Autodesk Fusion 360 part; units mm, degrees
(part 20 of 28)
  line L3105 (96.8519, 73.2833) -> (96.6596, 73.2451)
  line L3106 (96.6596, 73.2451) -> (96.4636, 73.2451)
  line L3107 (96.4636, 73.2451) -> (96.2713, 73.2833)
  line L3108 (96.2713, 73.2833) -> (96.0902, 73.3584)
  line L3109 (96.0902, 73.3584) -> (95.9272, 73.4673)
  line L3110 (95.9272, 73.4673) -> (95.7886, 73.6059)
  line L3111 (95.7886, 73.6059) -> (95.6797, 73.7689)
  line L3112 (95.6797, 73.7689) -> (95.6047, 73.95)
  line L3113 (95.6047, 73.95) -> (95.5664, 74.1423)
  line L3114 (95.5664, 74.1423) -> (95.5616, 74.2403)
  line L3115 (95.5616, 74.2403) -> (95.5616, 75.4403)
  line L3116 (95.5616, 75.4403) -> (95.5664, 75.5383)
  line L3117 (95.5664, 75.5383) -> (95.6047, 75.7306)
  line L3118 (95.6047, 75.7306) -> (95.6797, 75.9117)
  line L3119 (95.6797, 75.9117) -> (95.7886, 76.0747)
  line L3120 (95.7886, 76.0747) -> (95.9272, 76.2133)
  line L3121 (95.9272, 76.2133) -> (96.0902, 76.3222)
  line L3122 (96.0902, 76.3222) -> (96.2713, 76.3972)
  line L3123 (96.2713, 76.3972) -> (96.4636, 76.4355)
  line L3124 (96.4636, 76.4355) -> (96.6596, 76.4355)
  line L3125 (96.6596, 76.4355) -> (96.8519, 76.3972)
  line L3126 (99.5819, 76.3972) -> (99.763, 76.3222)
  line L3127 (99.763, 76.3222) -> (99.926, 76.2133)
  line L3128 (99.926, 76.2133) -> (100.0646, 76.0747)
  line L3129 (100.0646, 76.0747) -> (100.1735, 75.9117)
  line L3130 (100.1735, 75.9117) -> (100.2485, 75.7306)
  line L3131 (100.2485, 75.7306) -> (100.2868, 75.5383)
  line L3132 (100.2868, 75.5383) -> (100.2916, 75.4403)
  line L3133 (100.2916, 75.4403) -> (100.2916, 74.2403)
  line L3134 (100.2916, 74.2403) -> (100.2868, 74.1423)
  line L3135 (100.2868, 74.1423) -> (100.2485, 73.95)
  line L3136 (100.2485, 73.95) -> (100.1735, 73.7689)
  line L3137 (100.1735, 73.7689) -> (100.0646, 73.6059)
  line L3138 (100.0646, 73.6059) -> (99.926, 73.4673)
  line L3139 (99.926, 73.4673) -> (99.763, 73.3584)
  line L3140 (99.763, 73.3584) -> (99.5819, 73.2833)
  line L3141 (99.5819, 73.2833) -> (99.3896, 73.2451)
  line L3142 (99.3896, 73.2451) -> (99.1936, 73.2451)
  line L3143 (99.1936, 73.2451) -> (99.0013, 73.2833)
  line L3144 (99.0013, 73.2833) -> (98.8202, 73.3584)
  line L3145 (98.8202, 73.3584) -> (98.6572, 73.4673)
  line L3146 (98.6572, 73.4673) -> (98.5186, 73.6059)
  line L3147 (98.5186, 73.6059) -> (98.4097, 73.7689)
  line L3148 (98.4097, 73.7689) -> (98.3347, 73.95)
  line L3149 (98.3347, 73.95) -> (98.2964, 74.1423)
  line L3150 (98.2964, 74.1423) -> (98.2916, 74.2403)
  line L3151 (98.2916, 74.2403) -> (98.2916, 75.4403)
  line L3152 (98.2916, 75.4403) -> (98.2964, 75.5383)
  line L3153 (98.2964, 75.5383) -> (98.3347, 75.7306)
  line L3154 (98.3347, 75.7306) -> (98.4097, 75.9117)
  line L3155 (98.4097, 75.9117) -> (98.5186, 76.0747)
  line L3156 (98.5186, 76.0747) -> (98.6572, 76.2133)
  line L3157 (98.6572, 76.2133) -> (98.8202, 76.3222)
  line L3158 (98.8202, 76.3222) -> (99.0013, 76.3972)
  line L3159 (99.0013, 76.3972) -> (99.1936, 76.4355)
  line L3160 (99.1936, 76.4355) -> (99.3896, 76.4355)
  line L3161 (99.3896, 76.4355) -> (99.5819, 76.3972)
  line L3162 (131.7769, 76.3972) -> (131.958, 76.3222)
  line L3163 (131.958, 76.3222) -> (132.121, 76.2133)
  line L3164 (132.121, 76.2133) -> (132.2596, 76.0747)
  line L3165 (132.2596, 76.0747) -> (132.3685, 75.9117)
  line L3166 (132.3685, 75.9117) -> (132.4435, 75.7306)
  line L3167 (132.4435, 75.7306) -> (132.4818, 75.5383)
  line L3168 (132.4818, 75.5383) -> (132.4866, 75.4403)
  line L3169 (132.4866, 75.4403) -> (132.4866, 74.2403)
  line L3170 (132.4866, 74.2403) -> (132.4818, 74.1423)
  line L3171 (132.4818, 74.1423) -> (132.4435, 73.95)
  line L3172 (132.4435, 73.95) -> (132.3685, 73.7689)
  line L3173 (132.3685, 73.7689) -> (132.2596, 73.6059)
  line L3174 (132.2596, 73.6059) -> (132.121, 73.4673)
  line L3175 (132.121, 73.4673) -> (131.958, 73.3584)
  line L3176 (131.958, 73.3584) -> (131.7769, 73.2833)
  line L3177 (131.7769, 73.2833) -> (131.5846, 73.2451)
  line L3178 (131.5846, 73.2451) -> (131.3886, 73.2451)
  line L3179 (131.3886, 73.2451) -> (131.1963, 73.2833)
  line L3180 (131.1963, 73.2833) -> (131.0152, 73.3584)
  line L3181 (131.0152, 73.3584) -> (130.8522, 73.4673)
  line L3182 (130.8522, 73.4673) -> (130.7136, 73.6059)
  line L3183 (130.7136, 73.6059) -> (130.6047, 73.7689)
  line L3184 (130.6047, 73.7689) -> (130.5297, 73.95)
  line L3185 (130.5297, 73.95) -> (130.4914, 74.1423)
  line L3186 (130.4914, 74.1423) -> (130.4866, 74.2403)
  line L3187 (130.4866, 74.2403) -> (130.4866, 75.4403)
  line L3188 (130.4866, 75.4403) -> (130.4914, 75.5383)
  line L3189 (130.4914, 75.5383) -> (130.5297, 75.7306)
  line L3190 (130.5297, 75.7306) -> (130.6047, 75.9117)
  line L3191 (130.6047, 75.9117) -> (130.7136, 76.0747)
  line L3192 (130.7136, 76.0747) -> (130.8522, 76.2133)
  line L3193 (130.8522, 76.2133) -> (131.0152, 76.3222)
  line L3194 (131.0152, 76.3222) -> (131.1963, 76.3972)
  line L3195 (131.1963, 76.3972) -> (131.3886, 76.4355)
  line L3196 (131.3886, 76.4355) -> (131.5846, 76.4355)
  line L3197 (131.5846, 76.4355) -> (131.7769, 76.3972)
  line L3198 (134.5069, 76.3972) -> (134.688, 76.3222)
  line L3199 (134.688, 76.3222) -> (134.851, 76.2133)
  line L3200 (134.851, 76.2133) -> (134.9896, 76.0747)
  line L3201 (134.9896, 76.0747) -> (135.0985, 75.9117)
  line L3202 (135.0985, 75.9117) -> (135.1735, 75.7306)
  line L3203 (135.1735, 75.7306) -> (135.2118, 75.5383)
  line L3204 (135.2118, 75.5383) -> (135.2166, 75.4403)
  line L3205 (135.2166, 75.4403) -> (135.2166, 74.2403)
  line L3206 (135.2166, 74.2403) -> (135.2118, 74.1423)
  line L3207 (135.2118, 74.1423) -> (135.1735, 73.95)
  line L3208 (135.1735, 73.95) -> (135.0985, 73.7689)
  line L3209 (135.0985, 73.7689) -> (134.9896, 73.6059)
  line L3210 (134.9896, 73.6059) -> (134.851, 73.4673)
  line L3211 (134.851, 73.4673) -> (134.688, 73.3584)
  line L3212 (134.688, 73.3584) -> (134.5069, 73.2833)
  line L3213 (134.5069, 73.2833) -> (134.3146, 73.2451)
  line L3214 (134.3146, 73.2451) -> (134.1186, 73.2451)
  line L3215 (134.1186, 73.2451) -> (133.9263, 73.2833)
  line L3216 (133.9263, 73.2833) -> (133.7452, 73.3584)
  line L3217 (133.7452, 73.3584) -> (133.5822, 73.4673)
  line L3218 (133.5822, 73.4673) -> (133.4436, 73.6059)
  line L3219 (133.4436, 73.6059) -> (133.3347, 73.7689)
  line L3220 (133.3347, 73.7689) -> (133.2597, 73.95)
  line L3221 (133.2597, 73.95) -> (133.2214, 74.1423)
  line L3222 (133.2214, 74.1423) -> (133.2166, 74.2403)
  line L3223 (133.2166, 74.2403) -> (133.2166, 75.4403)
  line L3224 (133.2166, 75.4403) -> (133.2214, 75.5383)
  line L3225 (133.2214, 75.5383) -> (133.2597, 75.7306)
  line L3226 (133.2597, 75.7306) -> (133.3347, 75.9117)
  line L3227 (133.3347, 75.9117) -> (133.4436, 76.0747)
  line L3228 (133.4436, 76.0747) -> (133.5822, 76.2133)
  line L3229 (133.5822, 76.2133) -> (133.7452, 76.3222)
  line L3230 (133.7452, 76.3222) -> (133.9263, 76.3972)
  line L3231 (133.9263, 76.3972) -> (134.1186, 76.4355)
  line L3232 (134.1186, 76.4355) -> (134.3146, 76.4355)
  line L3233 (134.3146, 76.4355) -> (134.5069, 76.3972)
  line L3234 (14.4065, 73.2985) -> (12.4065, 73.2985)
  line L3235 (12.4065, 73.2985) -> (12.4065, 76.4985)
  line L3236 (12.4065, 76.4985) -> (14.4065, 76.4985)
  line L3237 (14.4065, 76.4985) -> (14.4065, 73.2985)
  line L3238 (49.3315, 73.2985) -> (47.3315, 73.2985)
  line L3239 (47.3315, 73.2985) -> (47.3315, 76.4985)
  line L3240 (47.3315, 76.4985) -> (49.3315, 76.4985)
  line L3241 (49.3315, 76.4985) -> (49.3315, 73.2985)
  line L3242 (84.2565, 73.2985) -> (82.2565, 73.2985)
  line L3243 (82.2565, 73.2985) -> (82.2565, 76.4985)
  line L3244 (82.2565, 76.4985) -> (84.2565, 76.4985)
  line L3245 (84.2565, 76.4985) -> (84.2565, 73.2985)
  line L3246 (119.1815, 73.2985) -> (117.1815, 73.2985)
  line L3247 (117.1815, 73.2985) -> (117.1815, 76.4985)
  line L3248 (117.1815, 76.4985) -> (119.1815, 76.4985)
  line L3249 (119.1815, 76.4985) -> (119.1815, 73.2985)
  line L3250 (16.4668, 76.4554) -> (16.6479, 76.3804)
  line L3251 (16.6479, 76.3804) -> (16.8109, 76.2715)
  line L3252 (16.8109, 76.2715) -> (16.9495, 76.1329)
  line L3253 (16.9495, 76.1329) -> (17.0584, 75.9699)
  line L3254 (17.0584, 75.9699) -> (17.1335, 75.7888)
  line L3255 (17.1335, 75.7888) -> (17.1717, 75.5965)
  line L3256 (17.1717, 75.5965) -> (17.1765, 75.4985)
  line L3257 (17.1765, 75.4985) -> (17.1765, 74.2985)
  line L3258 (17.1765, 74.2985) -> (17.1717, 74.2005)
  line L3259 (17.1717, 74.2005) -> (17.1335, 74.0082)
  line L3260 (17.1335, 74.0082) -> (17.0584, 73.8271)
  line L3261 (17.0584, 73.8271) -> (16.9495, 73.6641)
  line L3262 (16.9495, 73.6641) -> (16.8109, 73.5255)
  line L3263 (16.8109, 73.5255) -> (16.6479, 73.4166)
  line L3264 (16.6479, 73.4166) -> (16.4668, 73.3415)
  line L3265 (16.4668, 73.3415) -> (16.2745, 73.3033)
  line L3266 (16.2745, 73.3033) -> (16.0785, 73.3033)
  line L3267 (16.0785, 73.3033) -> (15.8862, 73.3415)
  line L3268 (15.8862, 73.3415) -> (15.7051, 73.4166)
  line L3269 (15.7051, 73.4166) -> (15.5421, 73.5255)
  line L3270 (15.5421, 73.5255) -> (15.4035, 73.6641)
  line L3271 (15.4035, 73.6641) -> (15.2946, 73.8271)
  line L3272 (15.2946, 73.8271) -> (15.2196, 74.0082)
  line L3273 (15.2196, 74.0082) -> (15.1813, 74.2005)
  line L3274 (15.1813, 74.2005) -> (15.1765, 74.2985)
  line L3275 (15.1765, 74.2985) -> (15.1765, 75.4985)
  line L3276 (15.1765, 75.4985) -> (15.1813, 75.5965)
  line L3277 (15.1813, 75.5965) -> (15.2196, 75.7888)
  line L3278 (15.2196, 75.7888) -> (15.2946, 75.9699)
  line L3279 (15.2946, 75.9699) -> (15.4035, 76.1329)
  line L3280 (15.4035, 76.1329) -> (15.5421, 76.2715)
  line L3281 (15.5421, 76.2715) -> (15.7051, 76.3804)
  line L3282 (15.7051, 76.3804) -> (15.8862, 76.4554)
  line L3283 (15.8862, 76.4554) -> (16.0785, 76.4937)
  line L3284 (16.0785, 76.4937) -> (16.2745, 76.4937)
  line L3285 (16.2745, 76.4937) -> (16.4668, 76.4554)
  line L3286 (19.1968, 76.4554) -> (19.3779, 76.3804)
  line L3287 (19.3779, 76.3804) -> (19.5409, 76.2715)
  line L3288 (19.5409, 76.2715) -> (19.6795, 76.1329)
  line L3289 (19.6795, 76.1329) -> (19.7884, 75.9699)
  line L3290 (19.7884, 75.9699) -> (19.8635, 75.7888)
  line L3291 (19.8635, 75.7888) -> (19.9017, 75.5965)
  line L3292 (19.9017, 75.5965) -> (19.9065, 75.4985)
  line L3293 (19.9065, 75.4985) -> (19.9065, 74.2985)
  line L3294 (19.9065, 74.2985) -> (19.9017, 74.2005)
  line L3295 (19.9017, 74.2005) -> (19.8635, 74.0082)
  line L3296 (19.8635, 74.0082) -> (19.7884, 73.8271)
  line L3297 (19.7884, 73.8271) -> (19.6795, 73.6641)
  line L3298 (19.6795, 73.6641) -> (19.5409, 73.5255)
  line L3299 (19.5409, 73.5255) -> (19.3779, 73.4166)
  line L3300 (19.3779, 73.4166) -> (19.1968, 73.3415)
  line L3301 (19.1968, 73.3415) -> (19.0045, 73.3033)
  line L3302 (19.0045, 73.3033) -> (18.8085, 73.3033)
  line L3303 (18.8085, 73.3033) -> (18.6162, 73.3415)
  line L3304 (18.6162, 73.3415) -> (18.4351, 73.4166)
  line L3305 (18.4351, 73.4166) -> (18.2721, 73.5255)
  line L3306 (18.2721, 73.5255) -> (18.1335, 73.6641)
  line L3307 (18.1335, 73.6641) -> (18.0246, 73.8271)
  line L3308 (18.0246, 73.8271) -> (17.9496, 74.0082)
  line L3309 (17.9496, 74.0082) -> (17.9113, 74.2005)
  line L3310 (17.9113, 74.2005) -> (17.9065, 74.2985)
  line L3311 (17.9065, 74.2985) -> (17.9065, 75.4985)
  line L3312 (17.9065, 75.4985) -> (17.9113, 75.5965)
  line L3313 (17.9113, 75.5965) -> (17.9496, 75.7888)
  line L3314 (17.9496, 75.7888) -> (18.0246, 75.9699)
  line L3315 (18.0246, 75.9699) -> (18.1335, 76.1329)
  line L3316 (18.1335, 76.1329) -> (18.2721, 76.2715)
  line L3317 (18.2721, 76.2715) -> (18.4351, 76.3804)
  line L3318 (18.4351, 76.3804) -> (18.6162, 76.4554)
  line L3319 (18.6162, 76.4554) -> (18.8085, 76.4937)
  line L3320 (18.8085, 76.4937) -> (19.0045, 76.4937)
  line L3321 (19.0045, 76.4937) -> (19.1968, 76.4554)
  line L3322 (51.3918, 76.4554) -> (51.5729, 76.3804)
  line L3323 (51.5729, 76.3804) -> (51.7359, 76.2715)
  line L3324 (51.7359, 76.2715) -> (51.8745, 76.1329)
  line L3325 (51.8745, 76.1329) -> (51.9834, 75.9699)
  line L3326 (51.9834, 75.9699) -> (52.0585, 75.7888)
  line L3327 (52.0585, 75.7888) -> (52.0967, 75.5965)
  line L3328 (52.0967, 75.5965) -> (52.1015, 75.4985)
  line L3329 (52.1015, 75.4985) -> (52.1015, 74.2985)
  line L3330 (52.1015, 74.2985) -> (52.0967, 74.2005)
  line L3331 (52.0967, 74.2005) -> (52.0585, 74.0082)
  line L3332 (52.0585, 74.0082) -> (51.9834, 73.8271)
  line L3333 (51.9834, 73.8271) -> (51.8745, 73.6641)
  line L3334 (51.8745, 73.6641) -> (51.7359, 73.5255)
  line L3335 (51.7359, 73.5255) -> (51.5729, 73.4166)
  line L3336 (51.5729, 73.4166) -> (51.3918, 73.3415)
  line L3337 (51.3918, 73.3415) -> (51.1995, 73.3033)
  line L3338 (51.1995, 73.3033) -> (51.0035, 73.3033)
  line L3339 (51.0035, 73.3033) -> (50.8112, 73.3415)
  line L3340 (50.8112, 73.3415) -> (50.6301, 73.4166)
  line L3341 (50.6301, 73.4166) -> (50.4671, 73.5255)
  line L3342 (50.4671, 73.5255) -> (50.3285, 73.6641)
  line L3343 (50.3285, 73.6641) -> (50.2196, 73.8271)
  line L3344 (50.2196, 73.8271) -> (50.1446, 74.0082)
  line L3345 (50.1446, 74.0082) -> (50.1063, 74.2005)
  line L3346 (50.1063, 74.2005) -> (50.1015, 74.2985)
  line L3347 (50.1015, 74.2985) -> (50.1015, 75.4985)
  line L3348 (50.1015, 75.4985) -> (50.1063, 75.5965)
  line L3349 (50.1063, 75.5965) -> (50.1446, 75.7888)
  line L3350 (50.1446, 75.7888) -> (50.2196, 75.9699)
  line L3351 (50.2196, 75.9699) -> (50.3285, 76.1329)
  line L3352 (50.3285, 76.1329) -> (50.4671, 76.2715)
  line L3353 (50.4671, 76.2715) -> (50.6301, 76.3804)
  line L3354 (50.6301, 76.3804) -> (50.8112, 76.4554)
  line L3355 (50.8112, 76.4554) -> (51.0035, 76.4937)
  line L3356 (51.0035, 76.4937) -> (51.1995, 76.4937)
  line L3357 (51.1995, 76.4937) -> (51.3918, 76.4554)
  line L3358 (54.1218, 76.4554) -> (54.3029, 76.3804)
  line L3359 (54.3029, 76.3804) -> (54.4659, 76.2715)
  line L3360 (54.4659, 76.2715) -> (54.6045, 76.1329)
  line L3361 (54.6045, 76.1329) -> (54.7134, 75.9699)
  line L3362 (54.7134, 75.9699) -> (54.7885, 75.7888)
  line L3363 (54.7885, 75.7888) -> (54.8267, 75.5965)
  line L3364 (54.8267, 75.5965) -> (54.8315, 75.4985)
  line L3365 (54.8315, 75.4985) -> (54.8315, 74.2985)
  line L3366 (54.8315, 74.2985) -> (54.8267, 74.2005)
  line L3367 (54.8267, 74.2005) -> (54.7885, 74.0082)
  line L3368 (54.7885, 74.0082) -> (54.7134, 73.8271)
  line L3369 (54.7134, 73.8271) -> (54.6045, 73.6641)
  line L3370 (54.6045, 73.6641) -> (54.4659, 73.5255)
  line L3371 (54.4659, 73.5255) -> (54.3029, 73.4166)
  line L3372 (54.3029, 73.4166) -> (54.1218, 73.3415)
  line L3373 (54.1218, 73.3415) -> (53.9295, 73.3033)
  line L3374 (53.9295, 73.3033) -> (53.7335, 73.3033)
  line L3375 (53.7335, 73.3033) -> (53.5412, 73.3415)
  line L3376 (53.5412, 73.3415) -> (53.3601, 73.4166)
  line L3377 (53.3601, 73.4166) -> (53.1971, 73.5255)
  line L3378 (53.1971, 73.5255) -> (53.0585, 73.6641)
  line L3379 (53.0585, 73.6641) -> (52.9496, 73.8271)
  line L3380 (52.9496, 73.8271) -> (52.8746, 74.0082)
  line L3381 (52.8746, 74.0082) -> (52.8363, 74.2005)
  line L3382 (52.8363, 74.2005) -> (52.8315, 74.2985)
  line L3383 (52.8315, 74.2985) -> (52.8315, 75.4985)
  line L3384 (52.8315, 75.4985) -> (52.8363, 75.5965)
  line L3385 (52.8363, 75.5965) -> (52.8746, 75.7888)
  line L3386 (52.8746, 75.7888) -> (52.9496, 75.9699)
  line L3387 (52.9496, 75.9699) -> (53.0585, 76.1329)
  line L3388 (53.0585, 76.1329) -> (53.1971, 76.2715)
  line L3389 (53.1971, 76.2715) -> (53.3601, 76.3804)
  line L3390 (53.3601, 76.3804) -> (53.5412, 76.4554)
  line L3391 (53.5412, 76.4554) -> (53.7335, 76.4937)
  line L3392 (53.7335, 76.4937) -> (53.9295, 76.4937)
  line L3393 (53.9295, 76.4937) -> (54.1218, 76.4554)
  line L3394 (86.3168, 76.4554) -> (86.4979, 76.3804)
  line L3395 (86.4979, 76.3804) -> (86.6609, 76.2715)
  line L3396 (86.6609, 76.2715) -> (86.7995, 76.1329)
  line L3397 (86.7995, 76.1329) -> (86.9084, 75.9699)
  line L3398 (86.9084, 75.9699) -> (86.9835, 75.7888)
  line L3399 (86.9835, 75.7888) -> (87.0217, 75.5965)
  line L3400 (87.0217, 75.5965) -> (87.0265, 75.4985)
  line L3401 (87.0265, 75.4985) -> (87.0265, 74.2985)
  line L3402 (87.0265, 74.2985) -> (87.0217, 74.2005)
  line L3403 (87.0217, 74.2005) -> (86.9835, 74.0082)
  line L3404 (86.9835, 74.0082) -> (86.9084, 73.8271)
  line L3405 (86.9084, 73.8271) -> (86.7995, 73.6641)
  line L3406 (86.7995, 73.6641) -> (86.6609, 73.5255)
  line L3407 (86.6609, 73.5255) -> (86.4979, 73.4166)
  line L3408 (86.4979, 73.4166) -> (86.3168, 73.3415)
  line L3409 (86.3168, 73.3415) -> (86.1245, 73.3033)
  line L3410 (86.1245, 73.3033) -> (85.9285, 73.3033)
  line L3411 (85.9285, 73.3033) -> (85.7362, 73.3415)
  line L3412 (85.7362, 73.3415) -> (85.5551, 73.4166)
  line L3413 (85.5551, 73.4166) -> (85.3921, 73.5255)
  line L3414 (85.3921, 73.5255) -> (85.2535, 73.6641)
  line L3415 (85.2535, 73.6641) -> (85.1446, 73.8271)
  line L3416 (85.1446, 73.8271) -> (85.0696, 74.0082)
  line L3417 (85.0696, 74.0082) -> (85.0313, 74.2005)
  line L3418 (85.0313, 74.2005) -> (85.0265, 74.2985)
  line L3419 (85.0265, 74.2985) -> (85.0265, 75.4985)
  line L3420 (85.0265, 75.4985) -> (85.0313, 75.5965)
  line L3421 (85.0313, 75.5965) -> (85.0696, 75.7888)
  line L3422 (85.0696, 75.7888) -> (85.1446, 75.9699)
  line L3423 (85.1446, 75.9699) -> (85.2535, 76.1329)
  line L3424 (85.2535, 76.1329) -> (85.3921, 76.2715)
  line L3425 (85.3921, 76.2715) -> (85.5551, 76.3804)
  line L3426 (85.5551, 76.3804) -> (85.7362, 76.4554)
  line L3427 (85.7362, 76.4554) -> (85.9285, 76.4937)
  line L3428 (85.9285, 76.4937) -> (86.1245, 76.4937)
  line L3429 (86.1245, 76.4937) -> (86.3168, 76.4554)
  line L3430 (89.0468, 76.4554) -> (89.2279, 76.3804)
  line L3431 (89.2279, 76.3804) -> (89.3909, 76.2715)
  line L3432 (89.3909, 76.2715) -> (89.5295, 76.1329)
  line L3433 (89.5295, 76.1329) -> (89.6384, 75.9699)
  line L3434 (89.6384, 75.9699) -> (89.7135, 75.7888)
  line L3435 (89.7135, 75.7888) -> (89.7517, 75.5965)
  line L3436 (89.7517, 75.5965) -> (89.7565, 75.4985)
  line L3437 (89.7565, 75.4985) -> (89.7565, 74.2985)
  line L3438 (89.7565, 74.2985) -> (89.7517, 74.2005)
  line L3439 (89.7517, 74.2005) -> (89.7135, 74.0082)
  line L3440 (89.7135, 74.0082) -> (89.6384, 73.8271)
  line L3441 (89.6384, 73.8271) -> (89.5295, 73.6641)
  line L3442 (89.5295, 73.6641) -> (89.3909, 73.5255)
  line L3443 (89.3909, 73.5255) -> (89.2279, 73.4166)
  line L3444 (89.2279, 73.4166) -> (89.0468, 73.3415)
  line L3445 (89.0468, 73.3415) -> (88.8545, 73.3033)
  line L3446 (88.8545, 73.3033) -> (88.6585, 73.3033)
  line L3447 (88.6585, 73.3033) -> (88.4662, 73.3415)
  line L3448 (88.4662, 73.3415) -> (88.2851, 73.4166)
  line L3449 (88.2851, 73.4166) -> (88.1221, 73.5255)
  line L3450 (88.1221, 73.5255) -> (87.9835, 73.6641)
  line L3451 (87.9835, 73.6641) -> (87.8746, 73.8271)
  line L3452 (87.8746, 73.8271) -> (87.7996, 74.0082)
  line L3453 (87.7996, 74.0082) -> (87.7613, 74.2005)
  line L3454 (87.7613, 74.2005) -> (87.7565, 74.2985)
  line L3455 (87.7565, 74.2985) -> (87.7565, 75.4985)
  line L3456 (87.7565, 75.4985) -> (87.7613, 75.5965)
  line L3457 (87.7613, 75.5965) -> (87.7996, 75.7888)
  line L3458 (87.7996, 75.7888) -> (87.8746, 75.9699)
  line L3459 (87.8746, 75.9699) -> (87.9835, 76.1329)
  line L3460 (87.9835, 76.1329) -> (88.1221, 76.2715)
  line L3461 (88.1221, 76.2715) -> (88.2851, 76.3804)
  line L3462 (88.2851, 76.3804) -> (88.4662, 76.4554)
  line L3463 (88.4662, 76.4554) -> (88.6585, 76.4937)
  line L3464 (88.6585, 76.4937) -> (88.8545, 76.4937)
  line L3465 (88.8545, 76.4937) -> (89.0468, 76.4554)
  line L3466 (121.2418, 76.4554) -> (121.4229, 76.3804)
  line L3467 (121.4229, 76.3804) -> (121.5859, 76.2715)
  line L3468 (121.5859, 76.2715) -> (121.7245, 76.1329)
  line L3469 (121.7245, 76.1329) -> (121.8334, 75.9699)
  line L3470 (121.8334, 75.9699) -> (121.9085, 75.7888)
  line L3471 (121.9085, 75.7888) -> (121.9467, 75.5965)
  line L3472 (121.9467, 75.5965) -> (121.9515, 75.4985)
  line L3473 (121.9515, 75.4985) -> (121.9515, 74.2985)
  line L3474 (121.9515, 74.2985) -> (121.9467, 74.2005)
  line L3475 (121.9467, 74.2005) -> (121.9085, 74.0082)
  line L3476 (121.9085, 74.0082) -> (121.8334, 73.8271)
  line L3477 (121.8334, 73.8271) -> (121.7245, 73.6641)
  line L3478 (121.7245, 73.6641) -> (121.5859, 73.5255)
  line L3479 (121.5859, 73.5255) -> (121.4229, 73.4166)
  line L3480 (121.4229, 73.4166) -> (121.2418, 73.3415)
  line L3481 (121.2418, 73.3415) -> (121.0495, 73.3033)
  line L3482 (121.0495, 73.3033) -> (120.8535, 73.3033)
  line L3483 (120.8535, 73.3033) -> (120.6612, 73.3415)
  line L3484 (120.6612, 73.3415) -> (120.4801, 73.4166)
  line L3485 (120.4801, 73.4166) -> (120.3171, 73.5255)
  line L3486 (120.3171, 73.5255) -> (120.1785, 73.6641)
  line L3487 (120.1785, 73.6641) -> (120.0696, 73.8271)
  line L3488 (120.0696, 73.8271) -> (119.9946, 74.0082)
  line L3489 (119.9946, 74.0082) -> (119.9563, 74.2005)
  line L3490 (119.9563, 74.2005) -> (119.9515, 74.2985)
  line L3491 (119.9515, 74.2985) -> (119.9515, 75.4985)
  line L3492 (119.9515, 75.4985) -> (119.9563, 75.5965)
  line L3493 (119.9563, 75.5965) -> (119.9946, 75.7888)
  line L3494 (119.9946, 75.7888) -> (120.0696, 75.9699)
  line L3495 (120.0696, 75.9699) -> (120.1785, 76.1329)
  line L3496 (120.1785, 76.1329) -> (120.3171, 76.2715)
  line L3497 (120.3171, 76.2715) -> (120.4801, 76.3804)
  line L3498 (120.4801, 76.3804) -> (120.6612, 76.4554)
  line L3499 (120.6612, 76.4554) -> (120.8535, 76.4937)
  line L3500 (120.8535, 76.4937) -> (121.0495, 76.4937)
  line L3501 (121.0495, 76.4937) -> (121.2418, 76.4554)
  line L3502 (123.9718, 76.4554) -> (124.1529, 76.3804)
  line L3503 (124.1529, 76.3804) -> (124.3159, 76.2715)
  line L3504 (124.3159, 76.2715) -> (124.4545, 76.1329)
  line L3505 (124.4545, 76.1329) -> (124.5634, 75.9699)
  line L3506 (124.5634, 75.9699) -> (124.6385, 75.7888)
  line L3507 (124.6385, 75.7888) -> (124.6767, 75.5965)
  line L3508 (124.6767, 75.5965) -> (124.6815, 75.4985)
  line L3509 (124.6815, 75.4985) -> (124.6815, 74.2985)
  line L3510 (124.6815, 74.2985) -> (124.6767, 74.2005)
  line L3511 (124.6767, 74.2005) -> (124.6385, 74.0082)
  line L3512 (124.6385, 74.0082) -> (124.5634, 73.8271)
  line L3513 (124.5634, 73.8271) -> (124.4545, 73.6641)
  line L3514 (124.4545, 73.6641) -> (124.3159, 73.5255)
  line L3515 (124.3159, 73.5255) -> (124.1529, 73.4166)
  line L3516 (124.1529, 73.4166) -> (123.9718, 73.3415)
  line L3517 (123.9718, 73.3415) -> (123.7795, 73.3033)
  line L3518 (123.7795, 73.3033) -> (123.5835, 73.3033)
  line L3519 (123.5835, 73.3033) -> (123.3912, 73.3415)
  line L3520 (123.3912, 73.3415) -> (123.2101, 73.4166)
  line L3521 (123.2101, 73.4166) -> (123.0471, 73.5255)
  line L3522 (123.0471, 73.5255) -> (122.9085, 73.6641)
  line L3523 (122.9085, 73.6641) -> (122.7996, 73.8271)
  line L3524 (122.7996, 73.8271) -> (122.7246, 74.0082)
  line L3525 (122.7246, 74.0082) -> (122.6863, 74.2005)
  line L3526 (122.6863, 74.2005) -> (122.6815, 74.2985)
  line L3527 (122.6815, 74.2985) -> (122.6815, 75.4985)
  line L3528 (122.6815, 75.4985) -> (122.6863, 75.5965)
  line L3529 (122.6863, 75.5965) -> (122.7246, 75.7888)
  line L3530 (122.7246, 75.7888) -> (122.7996, 75.9699)
  line L3531 (122.7996, 75.9699) -> (122.9085, 76.1329)
  line L3532 (122.9085, 76.1329) -> (123.0471, 76.2715)
  line L3533 (123.0471, 76.2715) -> (123.2101, 76.3804)
  line L3534 (123.2101, 76.3804) -> (123.3912, 76.4554)
  line L3535 (123.3912, 76.4554) -> (123.5835, 76.4937)
  line L3536 (123.5835, 76.4937) -> (123.7795, 76.4937)
  line L3537 (123.7795, 76.4937) -> (123.9718, 76.4554)
  line L3538 (14.4923, 82.8382) -> (14.686, 82.8075)
  line L3539 (14.686, 82.8075) -> (14.8725, 82.7469)
  line L3540 (14.8725, 82.7469) -> (15.0473, 82.6578)
  line L3541 (15.0473, 82.6578) -> (15.206, 82.5425)
  line L3542 (15.206, 82.5425) -> (15.3447, 82.4038)
  line L3543 (15.3447, 82.4038) -> (15.46, 82.2452)
  line L3544 (15.46, 82.2452) -> (15.549, 82.0704)
  line L3545 (15.549, 82.0704) -> (15.6096, 81.8838)
  line L3546 (15.6096, 81.8838) -> (15.6403, 81.6901)
  line L3547 (15.6403, 81.6901) -> (15.6403, 81.494)
  line L3548 (15.6403, 81.494) -> (15.6096, 81.3002)
  line L3549 (15.6096, 81.3002) -> (15.549, 81.1137)
  line L3550 (15.549, 81.1137) -> (15.46, 80.9389)
  line L3551 (15.46, 80.9389) -> (15.3447, 80.7802)
  line L3552 (15.3447, 80.7802) -> (15.206, 80.6415)
  line L3553 (15.206, 80.6415) -> (15.0473, 80.5262)
  line L3554 (15.0473, 80.5262) -> (14.8725, 80.4372)
  line L3555 (14.8725, 80.4372) -> (14.686, 80.3766)
  line L3556 (14.686, 80.3766) -> (14.4923, 80.3459)
  line L3557 (14.4923, 80.3459) -> (14.3942, 80.342)
  line L3558 (14.3942, 80.342) -> (13.8942, 80.342)
  line L3559 (13.8942, 80.342) -> (13.7961, 80.3459)
  line L3560 (13.7961, 80.3459) -> (13.6024, 80.3766)
  line L3561 (13.6024, 80.3766) -> (13.4158, 80.4372)
  line L3562 (13.4158, 80.4372) -> (13.2411, 80.5262)
  line L3563 (13.2411, 80.5262) -> (13.0824, 80.6415)
  line L3564 (13.0824, 80.6415) -> (12.9437, 80.7802)
  line L3565 (12.9437, 80.7802) -> (12.8284, 80.9389)
  line L3566 (12.8284, 80.9389) -> (12.7393, 81.1137)
  line L3567 (12.7393, 81.1137) -> (12.6787, 81.3002)
  line L3568 (12.6787, 81.3002) -> (12.648, 81.494)
  line L3569 (12.648, 81.494) -> (12.648, 81.6901)
  line L3570 (12.648, 81.6901) -> (12.6787, 81.8838)
  line L3571 (12.6787, 81.8838) -> (12.7393, 82.0704)
  line L3572 (12.7393, 82.0704) -> (12.8284, 82.2452)
  line L3573 (12.8284, 82.2452) -> (12.9437, 82.4038)
  line L3574 (12.9437, 82.4038) -> (13.0824, 82.5425)
  line L3575 (13.0824, 82.5425) -> (13.2411, 82.6578)
  line L3576 (13.2411, 82.6578) -> (13.4158, 82.7469)
  line L3577 (13.4158, 82.7469) -> (13.6024, 82.8075)
  line L3578 (13.6024, 82.8075) -> (13.7961, 82.8382)
  line L3579 (13.7961, 82.8382) -> (13.8942, 82.842)
  line L3580 (13.8942, 82.842) -> (14.3942, 82.842)
  line L3581 (14.3942, 82.842) -> (14.4923, 82.8382)
  line L3582 (22.1123, 82.8382) -> (22.306, 82.8075)
  line L3583 (22.306, 82.8075) -> (22.4925, 82.7469)
  line L3584 (22.4925, 82.7469) -> (22.6673, 82.6578)
  line L3585 (22.6673, 82.6578) -> (22.826, 82.5425)
  line L3586 (22.826, 82.5425) -> (22.9647, 82.4038)
  line L3587 (22.9647, 82.4038) -> (23.08, 82.2452)
  line L3588 (23.08, 82.2452) -> (23.169, 82.0704)
  line L3589 (23.169, 82.0704) -> (23.2296, 81.8838)
  line L3590 (23.2296, 81.8838) -> (23.2603, 81.6901)
  line L3591 (23.2603, 81.6901) -> (23.2603, 81.494)
  line L3592 (23.2603, 81.494) -> (23.2296, 81.3002)
  line L3593 (23.2296, 81.3002) -> (23.169, 81.1137)
  line L3594 (23.169, 81.1137) -> (23.08, 80.9389)
  line L3595 (23.08, 80.9389) -> (22.9647, 80.7802)
  line L3596 (22.9647, 80.7802) -> (22.826, 80.6415)
  line L3597 (22.826, 80.6415) -> (22.6673, 80.5262)
  line L3598 (22.6673, 80.5262) -> (22.4925, 80.4372)
  line L3599 (22.4925, 80.4372) -> (22.306, 80.3766)
  line L3600 (22.306, 80.3766) -> (22.1123, 80.3459)
  line L3601 (22.1123, 80.3459) -> (22.0142, 80.342)
  line L3602 (22.0142, 80.342) -> (21.5142, 80.342)
  line L3603 (21.5142, 80.342) -> (21.4161, 80.3459)
  line L3604 (21.4161, 80.3459) -> (21.2224, 80.3766)
  line L3605 (21.2224, 80.3766) -> (21.0358, 80.4372)
  line L3606 (21.0358, 80.4372) -> (20.8611, 80.5262)
  line L3607 (20.8611, 80.5262) -> (20.7024, 80.6415)
  line L3608 (20.7024, 80.6415) -> (20.5637, 80.7802)
  line L3609 (20.5637, 80.7802) -> (20.4484, 80.9389)
  line L3610 (20.4484, 80.9389) -> (20.3593, 81.1137)
  line L3611 (20.3593, 81.1137) -> (20.2987, 81.3002)
  line L3612 (20.2987, 81.3002) -> (20.268, 81.494)
  line L3613 (20.268, 81.494) -> (20.268, 81.6901)
  line L3614 (20.268, 81.6901) -> (20.2987, 81.8838)
  line L3615 (20.2987, 81.8838) -> (20.3593, 82.0704)
  line L3616 (20.3593, 82.0704) -> (20.4484, 82.2452)
  line L3617 (20.4484, 82.2452) -> (20.5637, 82.4038)
  line L3618 (20.5637, 82.4038) -> (20.7024, 82.5425)
  line L3619 (20.7024, 82.5425) -> (20.8611, 82.6578)
  line L3620 (20.8611, 82.6578) -> (21.0358, 82.7469)
  line L3621 (21.0358, 82.7469) -> (21.2224, 82.8075)
  line L3622 (21.2224, 82.8075) -> (21.4161, 82.8382)
  line L3623 (21.4161, 82.8382) -> (21.5142, 82.842)
  line L3624 (21.5142, 82.842) -> (22.0142, 82.842)
  line L3625 (22.0142, 82.842) -> (22.1123, 82.8382)
  line L3626 (49.4173, 82.8382) -> (49.611, 82.8075)
  line L3627 (49.611, 82.8075) -> (49.7975, 82.7469)
  line L3628 (49.7975, 82.7469) -> (49.9723, 82.6578)
  line L3629 (49.9723, 82.6578) -> (50.131, 82.5425)
  line L3630 (50.131, 82.5425) -> (50.2697, 82.4038)
  line L3631 (50.2697, 82.4038) -> (50.385, 82.2452)
  line L3632 (50.385, 82.2452) -> (50.474, 82.0704)
  line L3633 (50.474, 82.0704) -> (50.5346, 81.8838)
  line L3634 (50.5346, 81.8838) -> (50.5653, 81.6901)
  line L3635 (50.5653, 81.6901) -> (50.5653, 81.494)
  line L3636 (50.5653, 81.494) -> (50.5346, 81.3002)
  line L3637 (50.5346, 81.3002) -> (50.474, 81.1137)
  line L3638 (50.474, 81.1137) -> (50.385, 80.9389)
  line L3639 (50.385, 80.9389) -> (50.2697, 80.7802)
  line L3640 (50.2697, 80.7802) -> (50.131, 80.6415)
  line L3641 (50.131, 80.6415) -> (49.9723, 80.5262)
  line L3642 (49.9723, 80.5262) -> (49.7975, 80.4372)
  line L3643 (49.7975, 80.4372) -> (49.611, 80.3766)
  line L3644 (49.611, 80.3766) -> (49.4173, 80.3459)
  line L3645 (49.4173, 80.3459) -> (49.3192, 80.342)
  line L3646 (49.3192, 80.342) -> (48.8192, 80.342)
  line L3647 (48.8192, 80.342) -> (48.7211, 80.3459)
  line L3648 (48.7211, 80.3459) -> (48.5274, 80.3766)
  line L3649 (48.5274, 80.3766) -> (48.3408, 80.4372)
  line L3650 (48.3408, 80.4372) -> (48.1661, 80.5262)
  line L3651 (48.1661, 80.5262) -> (48.0074, 80.6415)
  line L3652 (48.0074, 80.6415) -> (47.8687, 80.7802)
  line L3653 (47.8687, 80.7802) -> (47.7534, 80.9389)
  line L3654 (47.7534, 80.9389) -> (47.6643, 81.1137)
  line L3655 (47.6643, 81.1137) -> (47.6037, 81.3002)
  line L3656 (47.6037, 81.3002) -> (47.573, 81.494)
  line L3657 (47.573, 81.494) -> (47.573, 81.6901)
  line L3658 (47.573, 81.6901) -> (47.6037, 81.8838)
  line L3659 (47.6037, 81.8838) -> (47.6643, 82.0704)
  line L3660 (47.6643, 82.0704) -> (47.7534, 82.2452)
  line L3661 (47.7534, 82.2452) -> (47.8687, 82.4038)
  line L3662 (47.8687, 82.4038) -> (48.0074, 82.5425)
  line L3663 (48.0074, 82.5425) -> (48.1661, 82.6578)
  line L3664 (48.1661, 82.6578) -> (48.3408, 82.7469)
  line L3665 (48.3408, 82.7469) -> (48.5274, 82.8075)
  line L3666 (48.5274, 82.8075) -> (48.7211, 82.8382)
  line L3667 (48.7211, 82.8382) -> (48.8192, 82.842)
  line L3668 (48.8192, 82.842) -> (49.3192, 82.842)
  line L3669 (49.3192, 82.842) -> (49.4173, 82.8382)
  line L3670 (57.0373, 82.8382) -> (57.231, 82.8075)
  line L3671 (57.231, 82.8075) -> (57.4175, 82.7469)
  line L3672 (57.4175, 82.7469) -> (57.5923, 82.6578)
  line L3673 (57.5923, 82.6578) -> (57.751, 82.5425)
  line L3674 (57.751, 82.5425) -> (57.8897, 82.4038)
  line L3675 (57.8897, 82.4038) -> (58.005, 82.2452)
  line L3676 (58.005, 82.2452) -> (58.094, 82.0704)
  line L3677 (58.094, 82.0704) -> (58.1546, 81.8838)
  line L3678 (58.1546, 81.8838) -> (58.1853, 81.6901)
  line L3679 (58.1853, 81.6901) -> (58.1853, 81.494)
  line L3680 (58.1853, 81.494) -> (58.1546, 81.3002)
  line L3681 (58.1546, 81.3002) -> (58.094, 81.1137)
  line L3682 (58.094, 81.1137) -> (58.005, 80.9389)
  line L3683 (58.005, 80.9389) -> (57.8897, 80.7802)
  line L3684 (57.8897, 80.7802) -> (57.751, 80.6415)
  line L3685 (57.751, 80.6415) -> (57.5923, 80.5262)
  line L3686 (57.5923, 80.5262) -> (57.4175, 80.4372)
  line L3687 (57.4175, 80.4372) -> (57.231, 80.3766)
  line L3688 (57.231, 80.3766) -> (57.0373, 80.3459)
  line L3689 (57.0373, 80.3459) -> (56.9392, 80.342)
  line L3690 (56.9392, 80.342) -> (56.4392, 80.342)
  line L3691 (56.4392, 80.342) -> (56.3411, 80.3459)
  line L3692 (56.3411, 80.3459) -> (56.1474, 80.3766)
  line L3693 (56.1474, 80.3766) -> (55.9608, 80.4372)
  line L3694 (55.9608, 80.4372) -> (55.7861, 80.5262)
  line L3695 (55.7861, 80.5262) -> (55.6274, 80.6415)
  line L3696 (55.6274, 80.6415) -> (55.4887, 80.7802)
  line L3697 (55.4887, 80.7802) -> (55.3734, 80.9389)
  line L3698 (55.3734, 80.9389) -> (55.2843, 81.1137)
  line L3699 (55.2843, 81.1137) -> (55.2237, 81.3002)
  line L3700 (55.2237, 81.3002) -> (55.193, 81.494)
  line L3701 (55.193, 81.494) -> (55.193, 81.6901)
  line L3702 (55.193, 81.6901) -> (55.2237, 81.8838)
  line L3703 (55.2237, 81.8838) -> (55.2843, 82.0704)
  line L3704 (55.2843, 82.0704) -> (55.3734, 82.2452)
  line L3705 (55.3734, 82.2452) -> (55.4887, 82.4038)
  line L3706 (55.4887, 82.4038) -> (55.6274, 82.5425)
  line L3707 (55.6274, 82.5425) -> (55.7861, 82.6578)
  line L3708 (55.7861, 82.6578) -> (55.9608, 82.7469)
  line L3709 (55.9608, 82.7469) -> (56.1474, 82.8075)
  line L3710 (56.1474, 82.8075) -> (56.3411, 82.8382)
  line L3711 (56.3411, 82.8382) -> (56.4392, 82.842)
  line L3712 (56.4392, 82.842) -> (56.9392, 82.842)
  line L3713 (56.9392, 82.842) -> (57.0373, 82.8382)
  line L3714 (84.3423, 82.8382) -> (84.536, 82.8075)
  line L3715 (84.536, 82.8075) -> (84.7225, 82.7469)
  line L3716 (84.7225, 82.7469) -> (84.8973, 82.6578)
  line L3717 (84.8973, 82.6578) -> (85.056, 82.5425)
  line L3718 (85.056, 82.5425) -> (85.1947, 82.4038)
  line L3719 (85.1947, 82.4038) -> (85.31, 82.2452)
  line L3720 (85.31, 82.2452) -> (85.399, 82.0704)
  line L3721 (85.399, 82.0704) -> (85.4596, 81.8838)
  line L3722 (85.4596, 81.8838) -> (85.4903, 81.6901)
  line L3723 (85.4903, 81.6901) -> (85.4903, 81.494)
  line L3724 (85.4903, 81.494) -> (85.4596, 81.3002)
  line L3725 (85.4596, 81.3002) -> (85.399, 81.1137)
  line L3726 (85.399, 81.1137) -> (85.31, 80.9389)
  line L3727 (85.31, 80.9389) -> (85.1947, 80.7802)
  line L3728 (85.1947, 80.7802) -> (85.056, 80.6415)
  line L3729 (85.056, 80.6415) -> (84.8973, 80.5262)
  line L3730 (84.8973, 80.5262) -> (84.7225, 80.4372)
  line L3731 (84.7225, 80.4372) -> (84.536, 80.3766)
  line L3732 (84.536, 80.3766) -> (84.3423, 80.3459)
  line L3733 (84.3423, 80.3459) -> (84.2442, 80.342)
  line L3734 (84.2442, 80.342) -> (83.7442, 80.342)
  line L3735 (83.7442, 80.342) -> (83.6461, 80.3459)
  line L3736 (83.6461, 80.3459) -> (83.4524, 80.3766)
  line L3737 (83.4524, 80.3766) -> (83.2658, 80.4372)
  line L3738 (83.2658, 80.4372) -> (83.0911, 80.5262)
  line L3739 (83.0911, 80.5262) -> (82.9324, 80.6415)
  line L3740 (82.9324, 80.6415) -> (82.7937, 80.7802)
  line L3741 (82.7937, 80.7802) -> (82.6784, 80.9389)
  line L3742 (82.6784, 80.9389) -> (82.5893, 81.1137)
  line L3743 (82.5893, 81.1137) -> (82.5287, 81.3002)
  line L3744 (82.5287, 81.3002) -> (82.498, 81.494)
  line L3745 (82.498, 81.494) -> (82.498, 81.6901)
  line L3746 (82.498, 81.6901) -> (82.5287, 81.8838)
  line L3747 (82.5287, 81.8838) -> (82.5893, 82.0704)
  line L3748 (82.5893, 82.0704) -> (82.6784, 82.2452)
  line L3749 (82.6784, 82.2452) -> (82.7937, 82.4038)
  line L3750 (82.7937, 82.4038) -> (82.9324, 82.5425)
  line L3751 (82.9324, 82.5425) -> (83.0911, 82.6578)
  line L3752 (83.0911, 82.6578) -> (83.2658, 82.7469)
  line L3753 (83.2658, 82.7469) -> (83.4524, 82.8075)
  line L3754 (83.4524, 82.8075) -> (83.6461, 82.8382)
  line L3755 (83.6461, 82.8382) -> (83.7442, 82.842)
  line L3756 (83.7442, 82.842) -> (84.2442, 82.842)
  line L3757 (84.2442, 82.842) -> (84.3423, 82.8382)
  line L3758 (91.9623, 82.8382) -> (92.156, 82.8075)
  line L3759 (92.156, 82.8075) -> (92.3425, 82.7469)
  line L3760 (92.3425, 82.7469) -> (92.5173, 82.6578)
  line L3761 (92.5173, 82.6578) -> (92.676, 82.5425)
  line L3762 (92.676, 82.5425) -> (92.8147, 82.4038)
  line L3763 (92.8147, 82.4038) -> (92.93, 82.2452)
  line L3764 (92.93, 82.2452) -> (93.019, 82.0704)
  line L3765 (93.019, 82.0704) -> (93.0796, 81.8838)
  line L3766 (93.0796, 81.8838) -> (93.1103, 81.6901)
  line L3767 (93.1103, 81.6901) -> (93.1103, 81.494)
  line L3768 (93.1103, 81.494) -> (93.0796, 81.3002)
  line L3769 (93.0796, 81.3002) -> (93.019, 81.1137)
  line L3770 (93.019, 81.1137) -> (92.93, 80.9389)
  line L3771 (92.93, 80.9389) -> (92.8147, 80.7802)
  line L3772 (92.8147, 80.7802) -> (92.676, 80.6415)
  line L3773 (92.676, 80.6415) -> (92.5173, 80.5262)
  line L3774 (92.5173, 80.5262) -> (92.3425, 80.4372)
  line L3775 (92.3425, 80.4372) -> (92.156, 80.3766)
  line L3776 (92.156, 80.3766) -> (91.9623, 80.3459)
  line L3777 (91.9623, 80.3459) -> (91.8642, 80.342)
  line L3778 (91.8642, 80.342) -> (91.3642, 80.342)
  line L3779 (91.3642, 80.342) -> (91.2661, 80.3459)
  line L3780 (91.2661, 80.3459) -> (91.0724, 80.3766)
  line L3781 (91.0724, 80.3766) -> (90.8858, 80.4372)
  line L3782 (90.8858, 80.4372) -> (90.7111, 80.5262)
  line L3783 (90.7111, 80.5262) -> (90.5524, 80.6415)
  line L3784 (90.5524, 80.6415) -> (90.4137, 80.7802)
  line L3785 (90.4137, 80.7802) -> (90.2984, 80.9389)
  line L3786 (90.2984, 80.9389) -> (90.2093, 81.1137)
  line L3787 (90.2093, 81.1137) -> (90.1487, 81.3002)
  line L3788 (90.1487, 81.3002) -> (90.118, 81.494)
  line L3789 (90.118, 81.494) -> (90.118, 81.6901)
  line L3790 (90.118, 81.6901) -> (90.1487, 81.8838)
  line L3791 (90.1487, 81.8838) -> (90.2093, 82.0704)
  line L3792 (90.2093, 82.0704) -> (90.2984, 82.2452)
  line L3793 (90.2984, 82.2452) -> (90.4137, 82.4038)
  line L3794 (90.4137, 82.4038) -> (90.5524, 82.5425)
  line L3795 (90.5524, 82.5425) -> (90.7111, 82.6578)
  line L3796 (90.7111, 82.6578) -> (90.8858, 82.7469)
  line L3797 (90.8858, 82.7469) -> (91.0724, 82.8075)
  line L3798 (91.0724, 82.8075) -> (91.2661, 82.8382)
  line L3799 (91.2661, 82.8382) -> (91.3642, 82.842)
  line L3800 (91.3642, 82.842) -> (91.8642, 82.842)
  line L3801 (91.8642, 82.842) -> (91.9623, 82.8382)
  line L3802 (119.2673, 82.8382) -> (119.461, 82.8075)
  line L3803 (119.461, 82.8075) -> (119.6475, 82.7469)
  line L3804 (119.6475, 82.7469) -> (119.8223, 82.6578)
  line L3805 (119.8223, 82.6578) -> (119.981, 82.5425)
  line L3806 (119.981, 82.5425) -> (120.1197, 82.4038)
  line L3807 (120.1197, 82.4038) -> (120.235, 82.2452)
  line L3808 (120.235, 82.2452) -> (120.324, 82.0704)
  line L3809 (120.324, 82.0704) -> (120.3846, 81.8838)
  line L3810 (120.3846, 81.8838) -> (120.4153, 81.6901)
  line L3811 (120.4153, 81.6901) -> (120.4153, 81.494)
  line L3812 (120.4153, 81.494) -> (120.3846, 81.3002)
  line L3813 (120.3846, 81.3002) -> (120.324, 81.1137)
  line L3814 (120.324, 81.1137) -> (120.235, 80.9389)
  line L3815 (120.235, 80.9389) -> (120.1197, 80.7802)
  line L3816 (120.1197, 80.7802) -> (119.981, 80.6415)
  line L3817 (119.981, 80.6415) -> (119.8223, 80.5262)
  line L3818 (119.8223, 80.5262) -> (119.6475, 80.4372)
  line L3819 (119.6475, 80.4372) -> (119.461, 80.3766)
  line L3820 (119.461, 80.3766) -> (119.2673, 80.3459)
  line L3821 (119.2673, 80.3459) -> (119.1692, 80.342)
  line L3822 (119.1692, 80.342) -> (118.6692, 80.342)
  line L3823 (118.6692, 80.342) -> (118.5711, 80.3459)
  line L3824 (118.5711, 80.3459) -> (118.3774, 80.3766)
  line L3825 (118.3774, 80.3766) -> (118.1908, 80.4372)
  line L3826 (118.1908, 80.4372) -> (118.0161, 80.5262)
  line L3827 (118.0161, 80.5262) -> (117.8574, 80.6415)
  line L3828 (117.8574, 80.6415) -> (117.7187, 80.7802)
  line L3829 (117.7187, 80.7802) -> (117.6034, 80.9389)
  line L3830 (117.6034, 80.9389) -> (117.5143, 81.1137)
  line L3831 (117.5143, 81.1137) -> (117.4537, 81.3002)
  line L3832 (117.4537, 81.3002) -> (117.423, 81.494)
  line L3833 (117.423, 81.494) -> (117.423, 81.6901)
  line L3834 (117.423, 81.6901) -> (117.4537, 81.8838)
  line L3835 (117.4537, 81.8838) -> (117.5143, 82.0704)
  line L3836 (117.5143, 82.0704) -> (117.6034, 82.2452)
  line L3837 (117.6034, 82.2452) -> (117.7187, 82.4038)
  line L3838 (117.7187, 82.4038) -> (117.8574, 82.5425)
  line L3839 (117.8574, 82.5425) -> (118.0161, 82.6578)
  line L3840 (118.0161, 82.6578) -> (118.1908, 82.7469)
  line L3841 (118.1908, 82.7469) -> (118.3774, 82.8075)
  line L3842 (118.3774, 82.8075) -> (118.5711, 82.8382)
  line L3843 (118.5711, 82.8382) -> (118.6692, 82.842)
  line L3844 (118.6692, 82.842) -> (119.1692, 82.842)
  line L3845 (119.1692, 82.842) -> (119.2673, 82.8382)
  line L3846 (126.8873, 82.8382) -> (127.081, 82.8075)
  line L3847 (127.081, 82.8075) -> (127.2675, 82.7469)
  line L3848 (127.2675, 82.7469) -> (127.4423, 82.6578)
  line L3849 (127.4423, 82.6578) -> (127.601, 82.5425)
  line L3850 (127.601, 82.5425) -> (127.7397, 82.4038)
  line L3851 (127.7397, 82.4038) -> (127.855, 82.2452)
  line L3852 (127.855, 82.2452) -> (127.944, 82.0704)
  line L3853 (127.944, 82.0704) -> (128.0046, 81.8838)
  line L3854 (128.0046, 81.8838) -> (128.0353, 81.6901)
  line L3855 (128.0353, 81.6901) -> (128.0353, 81.494)
  line L3856 (128.0353, 81.494) -> (128.0046, 81.3002)
  line L3857 (128.0046, 81.3002) -> (127.944, 81.1137)
  line L3858 (127.944, 81.1137) -> (127.855, 80.9389)
  line L3859 (127.855, 80.9389) -> (127.7397, 80.7802)
  line L3860 (127.7397, 80.7802) -> (127.601, 80.6415)
  line L3861 (127.601, 80.6415) -> (127.4423, 80.5262)
  line L3862 (127.4423, 80.5262) -> (127.2675, 80.4372)
  line L3863 (127.2675, 80.4372) -> (127.081, 80.3766)
  line L3864 (127.081, 80.3766) -> (126.8873, 80.3459)
  line L3865 (126.8873, 80.3459) -> (126.7892, 80.342)
  line L3866 (126.7892, 80.342) -> (126.2892, 80.342)
  line L3867 (126.2892, 80.342) -> (126.1911, 80.3459)
  line L3868 (126.1911, 80.3459) -> (125.9974, 80.3766)
  line L3869 (125.9974, 80.3766) -> (125.8108, 80.4372)
  line L3870 (125.8108, 80.4372) -> (125.6361, 80.5262)
  line L3871 (125.6361, 80.5262) -> (125.4774, 80.6415)
  line L3872 (125.4774, 80.6415) -> (125.3387, 80.7802)
  line L3873 (125.3387, 80.7802) -> (125.2234, 80.9389)
  line L3874 (125.2234, 80.9389) -> (125.1343, 81.1137)
  line L3875 (125.1343, 81.1137) -> (125.0737, 81.3002)
  line L3876 (125.0737, 81.3002) -> (125.043, 81.494)
  line L3877 (125.043, 81.494) -> (125.043, 81.6901)
  line L3878 (125.043, 81.6901) -> (125.0737, 81.8838)
  line L3879 (125.0737, 81.8838) -> (125.1343, 82.0704)
  line L3880 (125.1343, 82.0704) -> (125.2234, 82.2452)
  line L3881 (125.2234, 82.2452) -> (125.3387, 82.4038)
  line L3882 (125.3387, 82.4038) -> (125.4774, 82.5425)
  line L3883 (125.4774, 82.5425) -> (125.6361, 82.6578)
  line L3884 (125.6361, 82.6578) -> (125.8108, 82.7469)
  line L3885 (125.8108, 82.7469) -> (125.9974, 82.8075)
  line L3886 (125.9974, 82.8075) -> (126.1911, 82.8382)
  line L3887 (126.1911, 82.8382) -> (126.2892, 82.842)
  line L3888 (126.2892, 82.842) -> (126.7892, 82.842)
  line L3889 (126.7892, 82.842) -> (126.8873, 82.8382)
  line L3890 (33.8595, 85.903) -> (34.046, 85.8424)
  line L3891 (34.046, 85.8424) -> (34.2208, 85.7533)
  line L3892 (34.2208, 85.7533) -> (34.3795, 85.638)
  line L3893 (34.3795, 85.638) -> (34.5182, 85.4993)
  line L3894 (34.5182, 85.4993) -> (34.6335, 85.3407)
  line L3895 (34.6335, 85.3407) -> (34.7225, 85.1659)
  line L3896 (34.7225, 85.1659) -> (34.7832, 84.9793)
  line L3897 (34.7832, 84.9793) -> (34.8138, 84.7856)
  line L3898 (34.8138, 84.7856) -> (34.8177, 84.6875)
  line L3899 (34.8177, 84.6875) -> (34.8177, 84.1875)
  line L3900 (34.8177, 84.1875) -> (34.8138, 84.0895)
  line L3901 (34.8138, 84.0895) -> (34.7832, 83.8957)
  line L3902 (34.7832, 83.8957) -> (34.7225, 83.7092)
  line L3903 (34.7225, 83.7092) -> (34.6335, 83.5344)
  line L3904 (34.6335, 83.5344) -> (34.5182, 83.3757)
  line L3905 (34.5182, 83.3757) -> (34.3795, 83.237)
  line L3906 (34.3795, 83.237) -> (34.2208, 83.1217)
  line L3907 (34.2208, 83.1217) -> (34.046, 83.0327)
  line L3908 (34.046, 83.0327) -> (33.8595, 82.9721)
  line L3909 (33.8595, 82.9721) -> (33.6658, 82.9414)
  line L3910 (33.6658, 82.9414) -> (33.4696, 82.9414)
  line L3911 (33.4696, 82.9414) -> (33.2759, 82.9721)
  line L3912 (33.2759, 82.9721) -> (33.0893, 83.0327)
  line L3913 (33.0893, 83.0327) -> (32.9146, 83.1217)
  line L3914 (32.9146, 83.1217) -> (32.7559, 83.237)
  line L3915 (32.7559, 83.237) -> (32.6172, 83.3757)
  line L3916 (32.6172, 83.3757) -> (32.5019, 83.5344)
  line L3917 (32.5019, 83.5344) -> (32.4128, 83.7092)
  line L3918 (32.4128, 83.7092) -> (32.3522, 83.8957)
  line L3919 (32.3522, 83.8957) -> (32.3215, 84.0895)
  line L3920 (32.3215, 84.0895) -> (32.3177, 84.1875)
  line L3921 (32.3177, 84.1875) -> (32.3177, 84.6875)
  line L3922 (32.3177, 84.6875) -> (32.3215, 84.7856)
  line L3923 (32.3215, 84.7856) -> (32.3522, 84.9793)
  line L3924 (32.3522, 84.9793) -> (32.4128, 85.1659)
  line L3925 (32.4128, 85.1659) -> (32.5019, 85.3407)
  line L3926 (32.5019, 85.3407) -> (32.6172, 85.4993)
  line L3927 (32.6172, 85.4993) -> (32.7559, 85.638)
  line L3928 (32.7559, 85.638) -> (32.9146, 85.7533)
  line L3929 (32.9146, 85.7533) -> (33.0893, 85.8424)
  line L3930 (33.0893, 85.8424) -> (33.2759, 85.903)
  line L3931 (33.2759, 85.903) -> (33.4696, 85.9337)
  line L3932 (33.4696, 85.9337) -> (33.6658, 85.9337)
  line L3933 (33.6658, 85.9337) -> (33.8595, 85.903)
  line L3934 (68.7845, 85.903) -> (68.971, 85.8424)
  line L3935 (68.971, 85.8424) -> (69.1458, 85.7533)
  line L3936 (69.1458, 85.7533) -> (69.3045, 85.638)
  line L3937 (69.3045, 85.638) -> (69.4432, 85.4993)
  line L3938 (69.4432, 85.4993) -> (69.5585, 85.3407)
  line L3939 (69.5585, 85.3407) -> (69.6475, 85.1659)
  line L3940 (69.6475, 85.1659) -> (69.7082, 84.9793)
  line L3941 (69.7082, 84.9793) -> (69.7388, 84.7856)
  line L3942 (69.7388, 84.7856) -> (69.7427, 84.6875)
  line L3943 (69.7427, 84.6875) -> (69.7427, 84.1875)
  line L3944 (69.7427, 84.1875) -> (69.7388, 84.0895)
  line L3945 (69.7388, 84.0895) -> (69.7082, 83.8957)
  line L3946 (69.7082, 83.8957) -> (69.6475, 83.7092)
  line L3947 (69.6475, 83.7092) -> (69.5585, 83.5344)
  line L3948 (69.5585, 83.5344) -> (69.4432, 83.3757)
  line L3949 (69.4432, 83.3757) -> (69.3045, 83.237)
  line L3950 (69.3045, 83.237) -> (69.1458, 83.1217)
  line L3951 (69.1458, 83.1217) -> (68.971, 83.0327)
  line L3952 (68.971, 83.0327) -> (68.7845, 82.9721)
  line L3953 (68.7845, 82.9721) -> (68.5908, 82.9414)
  line L3954 (68.5908, 82.9414) -> (68.3946, 82.9414)
  line L3955 (68.3946, 82.9414) -> (68.2009, 82.9721)
  line L3956 (68.2009, 82.9721) -> (68.0143, 83.0327)
  line L3957 (68.0143, 83.0327) -> (67.8396, 83.1217)
  line L3958 (67.8396, 83.1217) -> (67.6809, 83.237)
  line L3959 (67.6809, 83.237) -> (67.5422, 83.3757)
  line L3960 (67.5422, 83.3757) -> (67.4269, 83.5344)
  line L3961 (67.4269, 83.5344) -> (67.3378, 83.7092)
  line L3962 (67.3378, 83.7092) -> (67.2772, 83.8957)
  line L3963 (67.2772, 83.8957) -> (67.2465, 84.0895)
  line L3964 (67.2465, 84.0895) -> (67.2427, 84.1875)
  line L3965 (67.2427, 84.1875) -> (67.2427, 84.6875)
  line L3966 (67.2427, 84.6875) -> (67.2465, 84.7856)
  line L3967 (67.2465, 84.7856) -> (67.2772, 84.9793)
  line L3968 (67.2772, 84.9793) -> (67.3378, 85.1659)
  line L3969 (67.3378, 85.1659) -> (67.4269, 85.3407)
  line L3970 (67.4269, 85.3407) -> (67.5422, 85.4993)
  line L3971 (67.5422, 85.4993) -> (67.6809, 85.638)
  line L3972 (67.6809, 85.638) -> (67.8396, 85.7533)
  line L3973 (67.8396, 85.7533) -> (68.0143, 85.8424)
  line L3974 (68.0143, 85.8424) -> (68.2009, 85.903)
  line L3975 (68.2009, 85.903) -> (68.3946, 85.9337)
  line L3976 (68.3946, 85.9337) -> (68.5908, 85.9337)
  line L3977 (68.5908, 85.9337) -> (68.7845, 85.903)
  line L3978 (103.7095, 85.903) -> (103.896, 85.8424)
  line L3979 (103.896, 85.8424) -> (104.0708, 85.7533)
  line L3980 (104.0708, 85.7533) -> (104.2295, 85.638)
  line L3981 (104.2295, 85.638) -> (104.3682, 85.4993)
  line L3982 (104.3682, 85.4993) -> (104.4835, 85.3407)
  line L3983 (104.4835, 85.3407) -> (104.5725, 85.1659)
  line L3984 (104.5725, 85.1659) -> (104.6332, 84.9793)
  line L3985 (104.6332, 84.9793) -> (104.6638, 84.7856)
  line L3986 (104.6638, 84.7856) -> (104.6677, 84.6875)
  line L3987 (104.6677, 84.6875) -> (104.6677, 84.1875)
  line L3988 (104.6677, 84.1875) -> (104.6638, 84.0895)
  line L3989 (104.6638, 84.0895) -> (104.6332, 83.8957)
  line L3990 (104.6332, 83.8957) -> (104.5725, 83.7092)
  line L3991 (104.5725, 83.7092) -> (104.4835, 83.5344)
  line L3992 (104.4835, 83.5344) -> (104.3682, 83.3757)
  line L3993 (104.3682, 83.3757) -> (104.2295, 83.237)
  line L3994 (104.2295, 83.237) -> (104.0708, 83.1217)
  line L3995 (104.0708, 83.1217) -> (103.896, 83.0327)
  line L3996 (103.896, 83.0327) -> (103.7095, 82.9721)
  line L3997 (103.7095, 82.9721) -> (103.5158, 82.9414)
  line L3998 (103.5158, 82.9414) -> (103.3196, 82.9414)
  line L3999 (103.3196, 82.9414) -> (103.1259, 82.9721)
  line L4000 (103.1259, 82.9721) -> (102.9393, 83.0327)
  line L4001 (102.9393, 83.0327) -> (102.7646, 83.1217)
  line L4002 (102.7646, 83.1217) -> (102.6059, 83.237)
  line L4003 (102.6059, 83.237) -> (102.4672, 83.3757)
  line L4004 (102.4672, 83.3757) -> (102.3519, 83.5344)
  line L4005 (102.3519, 83.5344) -> (102.2628, 83.7092)
  line L4006 (102.2628, 83.7092) -> (102.2022, 83.8957)
  line L4007 (102.2022, 83.8957) -> (102.1715, 84.0895)
  line L4008 (102.1715, 84.0895) -> (102.1677, 84.1875)
  line L4009 (102.1677, 84.1875) -> (102.1677, 84.6875)
  line L4010 (102.1677, 84.6875) -> (102.1715, 84.7856)
  line L4011 (102.1715, 84.7856) -> (102.2022, 84.9793)
  line L4012 (102.2022, 84.9793) -> (102.2628, 85.1659)
  line L4013 (102.2628, 85.1659) -> (102.3519, 85.3407)
  line L4014 (102.3519, 85.3407) -> (102.4672, 85.4993)
  line L4015 (102.4672, 85.4993) -> (102.6059, 85.638)
  line L4016 (102.6059, 85.638) -> (102.7646, 85.7533)
  line L4017 (102.7646, 85.7533) -> (102.9393, 85.8424)
  line L4018 (102.9393, 85.8424) -> (103.1259, 85.903)
  line L4019 (103.1259, 85.903) -> (103.3196, 85.9337)
  line L4020 (103.3196, 85.9337) -> (103.5158, 85.9337)
  line L4021 (103.5158, 85.9337) -> (103.7095, 85.903)
  line L4022 (138.6345, 85.903) -> (138.821, 85.8424)
  line L4023 (138.821, 85.8424) -> (138.9958, 85.7533)
  line L4024 (138.9958, 85.7533) -> (139.1545, 85.638)